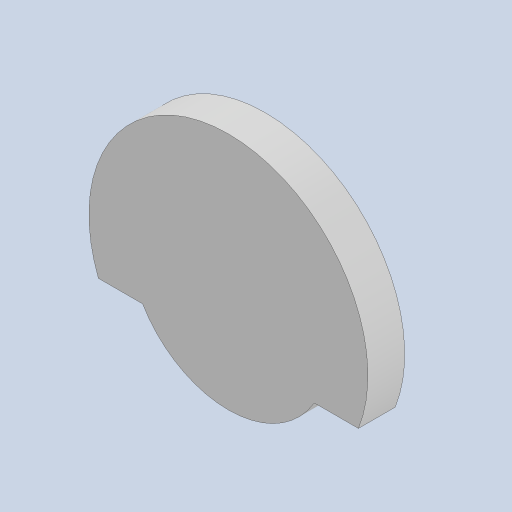
# Autodesk Inventor part: cage_hole_cover_01
Saved by Autodesk Inventor 2024.4 (Build 284460030, 460C)
## iProperties
Created: 2026-09-14
Part Number: cage_hole_cover_01
Material: Generic
Document SubType Name: Modeling
Designer: tooles01
Density: 1 g/cm^3
Appearance: Default
Author: tooles01
Autodesk Inventor part; units mm, degrees
ref_plane "YZ Plane" through (0, 0, 0) normal (1, 0, 0) x (0, 1, 0)
ref_plane "XZ Plane" through (0, 0, 0) normal (0, 1, 0) x (-1, 0, 0)
derived "cage_connector_03.ipt"
sketch "Sketch1: base" plane through (0, 0, 0) normal (0, 0, 1) x (1, 0, 0)
  circle A0 centre (-5, 4) radius 16.25
  circle A1 centre (-5, 4) radius 20.75
  circle A2 centre (-21, -12) radius 4.75
  circle A3 centre (11, -12) radius 4.75
  line L0 (-21, -12) -> (11, -12) construction
  line L1 (-21, 20) -> (-21, -12) construction
  point P0 (0, 0)
  point P1 (-5, -12)
  point P2 (-21, 4)
sketch "Sketch1: thru" plane through (0, 0, 0) normal (0, 0, 1) x (1, 0, 0)
  circle A0 centre (-5, 4) radius 16.25 projected
  point P0 (0, 0)
extrude "Ex1: thru" add sketch "Sketch1: thru" against normal blind 6
sketch "Sketch2: around" plane through (0, 0, 0) normal (0, 0, 1) x (1, 0, 0)
  circle A0 centre (-5, 4) radius 20.75 projected
  circle A1 centre (11, -12) radius 4.75 construction
  circle A2 centre (-21, -12) radius 4.75 construction
  circle A3 centre (-5, 4) radius 22.75
  line L0 (-26.2014, -4.25) -> (16.2014, -4.25)
  line L1 (-24.7737, -7.25) -> (14.7737, -7.25) construction
  point P0 (0, 0)
  point P1 (-24.0394, -4.25)
  point P2 (14.0394, -4.25)
  dimension "d10" = 2
  dimension "d31" = 3
  constraints: 4 end point, 4 point on circle, 2 tangent, 1 centre point, 1 coincident, 1 horizontal
  measures "d10" radial gap between concentric circles of A0 A3
  measures "d31" distance between parallel lines of L1 L0
extrude "Ex2: around" add sketch "Sketch2: around" against normal blind 3 contours A0 L0 A3 picked at (16.8763, 5.7597)
sketch "Sketch3: top face" plane through (0, 0, 0) normal (0, 0, 1) x (1, 0, 0)
  circle A0 centre (-5, 4) radius 20.75 projected
  line L0 (-26.2014, -4.25) -> (16.2014, -4.25) projected
  circle A1 centre (-5, 4) radius 16.25 projected
  circle A2 centre (-5, 4) radius 22.75 projected
  point P0 (0, 0)
  point P1 (-19, -4.25)
  point P2 (9, -4.25)
  point P3 (14.0394, -4.25)
  point P4 (-24.0394, -4.25)
extrude "Ex3: top face" add sketch "Sketch3: top face" along normal blind 3 contours A0 L0 A1 | A0 L0 A2 | A1 L0 | L0 A1 picked at (14.0571, 5.6219) picked at (16.8763, 5.7597)
ref_plane "Work Plane1" through (-5, 4, -6) normal (0, 0, 1) x (1, 0, 0)
sketch "Sketch4: text" plane through (-10, 0, -6) normal (0, 0, -1) x (-1, 0, 0)
  line L0 (-6.75, 5.75) -> (-3.25, 5.75) construction
  line L1 (-3.25, 5.75) -> (-3.25, 2.25) construction
  line L2 (-3.25, 2.25) -> (-6.75, 2.25) construction
  line L3 (-6.75, 2.25) -> (-6.75, 5.75) construction
  line L4 (-7.7183, 4.659) -> (-6.8376, 4.659)
  line L5 (-6.8376, 4.659) -> (-6.4061, 3.2588)
  line L6 (-6.4061, 3.2588) -> (-5.9628, 4.659)
  line L7 (-5.9628, 4.659) -> (-5.1086, 4.659)
  line L8 (-5.1086, 4.659) -> (-6.048, 2.4486)
  line L9 (-6.048, 2.4486) -> (-6.7995, 2.4486)
  line L10 (-6.7995, 2.4486) -> (-7.7183, 4.659)
  line L11 (-3.0244, 5.5514) -> (-3.0244, 2.4486)
  line L12 (-3.0244, 2.4486) -> (-3.8816, 2.4486)
  line L13 (-3.8816, 2.4486) -> (-3.8816, 4.4829)
  spline S0 degree 2 poles (-3.8816, 4.4829) (-4.09, 4.3244) (-4.4775, 4.1306) (-4.771, 4.0396) knots 0 0 0 1 2 2 2
  line L14 (-4.771, 4.0396) -> (-4.771, 4.7353)
  spline S1 degree 2 poles (-4.771, 4.7353) (-4.3395, 4.8733) (-3.861, 5.2637) (-3.726, 5.5514) knots 0 0 0 1 2 2 2
  line L15 (-3.726, 5.5514) -> (-3.0244, 5.5514)
  point P0 (-10, 0)
  point P1 (-3.25, 4)
  point P2 (-5, 4)
  point P3 (-5, 5.75)
  dimension "d30" = 3.5
  constraints: 2 midpoint, 1 horizontal, 1 horizontal alignment, 1 perpendicular, 1 vertical alignment, 2 other
  measures "d30" distance of L0.start L0.end
extrude "Ex4: text" cut sketch "Sketch4: text" against normal blind 1 from surface at 0
equation "\"d8\" = d5"
equation "\"d30\" = d22"
equation "\"d5\" = 6"
equation "\"d22\" = 3.5"
body "Solid1"
